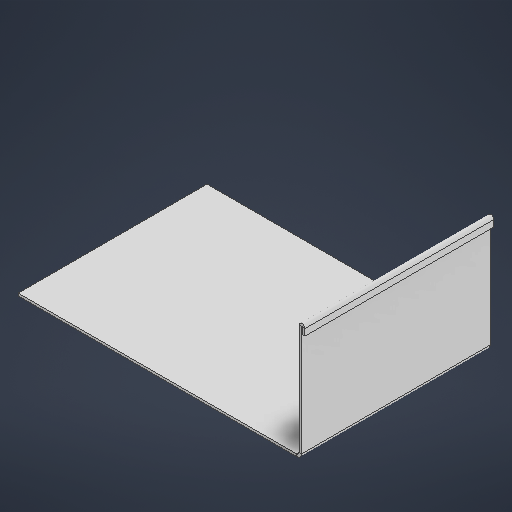
# Autodesk Inventor part: sm_hem
Saved by Autodesk Inventor 2027 (Build 310192060, 192F)
## iProperties
Created: 2026-10-20
Part Number: sm_hem
Material: Generic
Document SubType Name: Sheet Metal
Designer: vmiguel
Density: 1 g/cm^3
Sheet Metal Rule: Default_mm
Appearance: Default
Author: vmiguel
Autodesk Inventor part; units mm, degrees
ref_plane "YZ Plane" through (0, 0, 0) normal (1, 0, 0) x (0, 1, 0)
ref_plane "XZ Plane" through (0, 0, 0) normal (0, 1, 0) x (-1, 0, 0)
ref_plane "XY Plane" through (0, 0, 0) normal (0, 0, 1) x (1, 0, 0)
sketch "Sketch1" plane through (0, 0, 0) normal (0, 1, 0) x (-1, 0, 0)
  line L0 (0, 0) -> (60, 0)
  line L1 (60, 0) -> (60, -40)
  line L2 (60, -40) -> (0, -40)
  line L3 (0, -40) -> (0, 0)
  dimension "d0" = 60
  dimension "d1" = 40
  measures "d0" distance of L1.end L2.end
  measures "d1" distance of L0.end L1.end
extrude "Plate1" add sketch "Sketch1" along normal blind 0.5
sketch "Sketch2" plane through (-0.5, 0, -40) normal (1, 0, 0) x (0, 1, 0)
  line L0 (0, 40) -> (0, 0)
  line L1 (0, 0) -> (25, 0)
  line L2 (25, 0) -> (25, 40)
  line L3 (25, 40) -> (0, 40)
  constraints: 6 end point, 1 horizontal, 1 perpendicular, 1 vertical
edge flange "Flange1" height 25 angle 90 thickness 0.5 bend radius 0.5 thickness toward (1, 0, 0) relief straight relief width 0.5 relief depth 0.25 edges at (0, 0.5, -20) wall of the first edge with corners at (-0.5, 0, 0) (-0.5, 0, -40) (-0.5, 25, -40) (-0.5, 25, 0)
bend "Bend1"
corner "Corner1"
sketch "Sketch3" plane through (0, 24.375, -40) normal (0, 0, -1) x (-1, 0, 0)
  line L0 (0.5, 0) -> (0, 0)
  arc A0 (0, 0) -> (-0.25, 0) centre (-0.125, 0) ccw
  line L1 (-0.25, 0) -> (-0.25, -1.375)
  line L2 (-0.25, -1.375) -> (-0.75, -1.375)
  line L3 (-0.75, -1.375) -> (-0.75, 0)
  arc A1 (0.5, 0) -> (-0.75, 0) centre (-0.125, 0) ccw
  constraints: 8 end point, 4 point on circle
hem "Hem1" sketch "Sketch3" thickness 0.5 along (0, 0, 1) edges at (0, 25, -20)
equation "\"d2\" = Thickness"
equation "\"d13\" = BendReliefWidth"
equation "\"d14\" = BendReliefDepth"
equation "\"d15\" = MinimumRemnant"
equation "\"d16\" = TransitionRadius"
equation "\"d17\" = 4 * Thickness"
equation "\"d18\" = 0.5 * Thickness"
equation "\"d19\" = 0.5 * d18"
equation "\"d3\" = BendReliefWidth"
equation "\"d4\" = BendReliefDepth"
equation "\"d5\" = MinimumRemnant"
equation "\"d6\" = TransitionRadius"
equation "\"d9\" = BendRadius"
equation "\"d10\" = CornerReliefSize"
equation "\"d11\" = GapSize"
equation "\"d12\" = JacobiRadiusSize"
equation "\"BendRadius\" = Thickness"
equation "\"BendReliefWidth\" = Thickness"
equation "\"BendReliefDepth\" = 0.5 * Thickness"
equation "\"CornerReliefSize\" = 4 * Thickness"
equation "\"MinimumRemnant\" = 2 * Thickness"
equation "\"TransitionRadius\" = BendRadius"
equation "\"JacobiRadiusSize\" = BendRadius"
equation "\"GapSize\" = Thickness"
equation "\"Thickness\" = 0.5"
body "Solid1"
